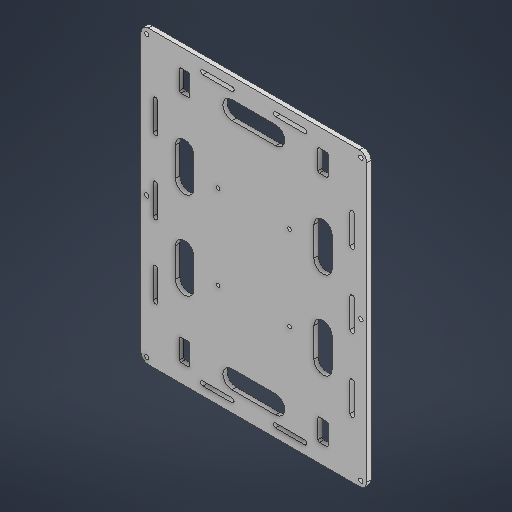
# Autodesk Inventor part: Top
Saved by Autodesk Inventor 2026.3 (Build 303398000, 398)
## iProperties
Created: 2026-07-17
Part Number: Top
Material: Generic
Document SubType Name: Modeling
Designer: nose
Density: 1 g/cm^3
Appearance: Default
Author: nose
Autodesk Inventor part; units mm, degrees
ref_plane "YZ Plane" through (0, 0, 0) normal (1, 0, 0) x (0, 1, 0)
ref_plane "XZ Plane" through (0, 0, 0) normal (0, 1, 0) x (-1, 0, 0)
ref_plane "XY Plane" through (0, 0, 0) normal (0, 0, 1) x (1, 0, 0)
sketch "Sketch1" plane through (0, 0, 0) normal (0, 0, 1) x (1, 0, 0)
  line L0 (72.5, -100) -> (-72.5, -100)
  line L1 (-77.5, -95) -> (-77.5, 95)
  line L2 (-72.5, 100) -> (72.5, 100)
  line L3 (77.5, 95) -> (77.5, -95)
  line L4 (77.5, -100) -> (-77.5, 100) construction
  line L5 (-77.5, -100) -> (77.5, 100) construction
  arc A0 (-72.5, 100) -> (-77.5, 95) centre (-72.5, 95) ccw
  arc A1 (77.5, 95) -> (72.5, 100) centre (72.5, 95) ccw
  arc A2 (72.5, -100) -> (77.5, -95) centre (72.5, -95) ccw
  arc A3 (-77.5, -95) -> (-72.5, -100) centre (-72.5, -95) ccw
  point P0 (0, 0)
  dimension "d0" = 155
  dimension "d1" = 200
  dimension "d2" = 5
  constraints: 12 end point, 8 point on circle, 8 point on line, 8 tangent, 4 centre point, 3 equal radius, 2 midpoint, 2 parallel, 1 horizontal, 1 perpendicular
  measures "d0" distance of L4.end L5.end
  measures "d1" distance of L5.start L4.end
  measures "d2" radius of A0
extrude "base" add sketch "Sketch1" along normal blind 3
sketch "Sketch2" plane through (0, 0, 3) normal (0, 0, 1) x (1, 0, 0)
  line L0 (-90.3018, 80) -> (-26.5899, 80) construction
  line L1 (-63.5, 59.4965) -> (-63.5, 108.4491) construction
  line L2 (-45, 72.5) -> (-50, 72.5)
  line L3 (-51, 73.5) -> (-51, 86.5)
  line L4 (-50, 87.5) -> (-45, 87.5)
  line L5 (-44, 86.5) -> (-44, 73.5)
  line L6 (-44, 72.5) -> (-51, 87.5) construction
  line L7 (-51, 72.5) -> (-44, 87.5) construction
  arc A0 (-50, 87.5) -> (-51, 86.5) centre (-50, 86.5) ccw
  arc A1 (-44, 86.5) -> (-45, 87.5) centre (-45, 86.5) ccw
  arc A2 (-45, 72.5) -> (-44, 73.5) centre (-45, 73.5) ccw
  arc A3 (-51, 73.5) -> (-50, 72.5) centre (-50, 73.5) ccw
  line L8 (0, -165.9432) -> (0, 165.9432) construction
  line L9 (-120.5021, 0) -> (120.5021, 0) construction
  arc A4 (50, 72.5) -> (51, 73.5) centre (50, 73.5) ccw
  line L10 (45, 72.5) -> (50, 72.5)
  line L11 (51, 73.5) -> (51, 86.5)
  arc A5 (51, 86.5) -> (50, 87.5) centre (50, 86.5) ccw
  line L12 (44, 86.5) -> (44, 73.5)
  line L13 (50, 87.5) -> (45, 87.5)
  line L14 (51, 72.5) -> (44, 87.5) construction
  line L15 (44, 72.5) -> (51, 87.5) construction
  arc A6 (45, 87.5) -> (44, 86.5) centre (45, 86.5) ccw
  arc A7 (44, 73.5) -> (45, 72.5) centre (45, 73.5) ccw
  line L16 (45, -72.5) -> (50, -72.5)
  line L17 (-45, -72.5) -> (-50, -72.5)
  line L18 (-44, -86.5) -> (-44, -73.5)
  line L19 (-50, -87.5) -> (-45, -87.5)
  line L20 (-51, -73.5) -> (-51, -86.5)
  line L21 (-44, -72.5) -> (-51, -87.5) construction
  arc A8 (51, -73.5) -> (50, -72.5) centre (50, -73.5) ccw
  arc A9 (45, -72.5) -> (44, -73.5) centre (45, -73.5) ccw
  line L22 (51, -73.5) -> (51, -86.5)
  line L23 (44, -86.5) -> (44, -73.5)
  line L24 (50, -87.5) -> (45, -87.5)
  line L25 (51, -72.5) -> (44, -87.5) construction
  arc A10 (50, -87.5) -> (51, -86.5) centre (50, -86.5) ccw
  arc A11 (44, -86.5) -> (45, -87.5) centre (45, -86.5) ccw
  line L26 (44, -72.5) -> (51, -87.5) construction
  arc A12 (-44, -73.5) -> (-45, -72.5) centre (-45, -73.5) ccw
  arc A13 (-45, -87.5) -> (-44, -86.5) centre (-45, -86.5) ccw
  line L27 (-51, -72.5) -> (-44, -87.5) construction
  arc A14 (-51, -86.5) -> (-50, -87.5) centre (-50, -86.5) ccw
  arc A15 (-50, -72.5) -> (-51, -73.5) centre (-50, -73.5) ccw
  point P0 (0, 0)
  point P1 (-47.5, 80)
  point P2 (-47.5, 72.5)
  point P3 (47.5, 72.5)
  point P4 (47.5, 80)
  point P5 (63.5, 59.4965)
  point P6 (47.5, -72.5)
  point P7 (-26.5899, -80)
  point P8 (-47.5, -80)
  point P9 (47.5, -80)
  point P10 (-47.5, -72.5)
  dimension "d12" = 63.5
  dimension "d13" = 80
  dimension "d11" = 7
  dimension "d9" = 15
  dimension "d8" = 1
  dimension "d7" = 1
  dimension "d6" = 1
  dimension "d5" = 1
  constraints: 56 end point, 56 symmetric about line, 33 point on line, 32 point on circle, 16 centre point, 8 tangent, 5 midpoint, 3 horizontal, 2 parallel, 2 vertical, 1 perpendicular, 12 other
  measures "d12" distance from line of point (0, 0) L1
  measures "d13" distance from line of point (0, 0) L0
  measures "d11" distance of L6.end L7.end
  measures "d9" distance from line of point (-47.5, 72.5) L4
  measures "d8" radius of A0
  measures "d7" radius of A1
  measures "d6" radius of A2
  measures "d5" radius of A3
extrude "motor_mount" cut sketch "Sketch2" against normal through all
sketch "Sketch4" plane through (0, 0, 3) normal (0, 0, 1) x (1, 0, 0)
  line L0 (24.5, -29) -> (-24.5, -29) construction
  line L1 (-24.5, -29) -> (-24.5, 29) construction
  line L2 (-24.5, 29) -> (24.5, 29) construction
  line L3 (24.5, 29) -> (24.5, -29) construction
  line L4 (24.5, -29) -> (-24.5, 29) construction
  line L5 (-24.5, -29) -> (24.5, 29) construction
  circle A0 centre (-24.5, 29) radius 1.25
  circle A1 centre (-24.5, -29) radius 1.25
  circle A2 centre (24.5, -29) radius 1.25
  circle A3 centre (24.5, 29) radius 1.25
  point P0 (0, 0)
  dimension "d32" = 49
  dimension "d33" = 58
  dimension "d34" = 2.5
  dimension "d35" = 2.5
  dimension "d36" = 2.5
  dimension "d37" = 2.5
  constraints: 12 end point, 4 centre point, 4 coincident, 2 midpoint, 2 parallel, 1 horizontal, 1 perpendicular
  measures "d32" distance of L1.end L2.end
  measures "d33" distance of L0.end L1.end
  measures "d34" diameter of A0
  measures "d35" diameter of A1
  measures "d36" diameter of A2
  measures "d37" diameter of A3
extrude "rpi_mount" cut sketch "Sketch4" against normal through all
sketch "Sketch5" plane through (0, 0, 3) normal (0, 0, 1) x (1, 0, 0)
  line L0 (-15, 80) -> (15, 80) construction
  line L1 (-15, 73.75) -> (15, 73.75)
  line L2 (15, 86.25) -> (-15, 86.25)
  arc A0 (-15, 86.25) -> (-15, 73.75) centre (-15, 80) ccw
  arc A1 (15, 73.75) -> (15, 86.25) centre (15, 80) ccw
  line L3 (-47.5, 20) -> (-47.5, 40) construction
  line L4 (-41.25, 20) -> (-41.25, 40)
  line L5 (-53.75, 40) -> (-53.75, 20)
  arc A2 (-53.75, 20) -> (-41.25, 20) centre (-47.5, 20) ccw
  arc A3 (-41.25, 40) -> (-53.75, 40) centre (-47.5, 40) ccw
  line L6 (-47.5, 30) -> (-27.5, 30) construction
  line L7 (-77.5, 95) -> (-77.5, -95) projected
  line L8 (72.5, 100) -> (-72.5, 100) projected
  line L9 (0, 164.0736) -> (0, -168.6299) construction
  line L10 (-194.4712, 0) -> (266.7344, 0) construction
  line L11 (-15, -80) -> (15, -80) construction
  line L12 (-15, -73.75) -> (15, -73.75)
  line L13 (15, -86.25) -> (-15, -86.25)
  arc A4 (-15, -73.75) -> (-15, -86.25) centre (-15, -80) ccw
  arc A5 (15, -86.25) -> (15, -73.75) centre (15, -80) ccw
  line L14 (-47.5, -20) -> (-47.5, -40) construction
  line L15 (-41.25, -20) -> (-41.25, -40)
  line L16 (-53.75, -40) -> (-53.75, -20)
  arc A6 (-41.25, -20) -> (-53.75, -20) centre (-47.5, -20) ccw
  arc A7 (-53.75, -40) -> (-41.25, -40) centre (-47.5, -40) ccw
  line L17 (-47.5, -30) -> (-27.5, -30) construction
  line L18 (0, -164.0736) -> (0, 168.6299) construction
  line L19 (47.5, 20) -> (47.5, 40) construction
  line L20 (41.25, 20) -> (41.25, 40)
  line L21 (53.75, 40) -> (53.75, 20)
  arc A8 (41.25, 20) -> (53.75, 20) centre (47.5, 20) ccw
  arc A9 (53.75, 40) -> (41.25, 40) centre (47.5, 40) ccw
  line L22 (47.5, 30) -> (27.5, 30) construction
  line L23 (194.4712, 0) -> (-266.7344, 0) construction
  line L24 (47.5, -20) -> (47.5, -40) construction
  line L25 (41.25, -20) -> (41.25, -40)
  line L26 (53.75, -40) -> (53.75, -20)
  arc A10 (41.25, -40) -> (53.75, -40) centre (47.5, -40) ccw
  arc A11 (53.75, -20) -> (41.25, -20) centre (47.5, -20) ccw
  line L27 (47.5, -30) -> (27.5, -30) construction
  point P0 (0, 0)
  point P1 (0, 80)
  point P2 (0, -80)
  dimension "d40" = 15
  dimension "d41" = 12.5
  dimension "d42" = 10
  dimension "d44" = 12.5
  dimension "d45" = 30
  dimension "d46" = 20
  dimension "d47" = 30
  constraints: 64 end point, 35 symmetric about line, 24 point on circle, 12 centre point, 8 tangent, 3 horizontal, 2 midpoint, 2 parallel, 2 vertical, 1 perpendicular, 8 other
  measures "d40" distance of point (0, 80) L0.end
  measures "d41" diameter of A1
  measures "d42" distance of L6.start L3.end
  measures "d44" diameter of A3
  measures "d45" distance from line of L7 L6.start
  measures "d46" distance between parallel lines of L8 L0
  measures "d47" vertical distance of point (0, 0) L6.start
extrude "cable_hole" cut sketch "Sketch5" against normal through all
sketch "Sketch6" plane through (0, 0, 3) normal (0, 0, 1) x (1, 0, 0)
  line L0 (-67.5, -10) -> (-67.5, 10) construction
  line L1 (-66, -10) -> (-66, 10)
  line L2 (-69, 10) -> (-69, -10)
  arc A0 (-69, -10) -> (-66, -10) centre (-67.5, -10) ccw
  arc A1 (-66, 10) -> (-69, 10) centre (-67.5, 10) ccw
  line L3 (-67.5, -100) -> (-67.5, 100) construction
  line L4 (72.5, 100) -> (-72.5, 100) projected
  line L5 (-77.5, 95) -> (-77.5, -95) projected
  line L6 (-67.5, 40) -> (-67.5, 60) construction
  line L7 (-66, 40) -> (-66, 60)
  line L8 (-69, 60) -> (-69, 40)
  arc A2 (-69, 40) -> (-66, 40) centre (-67.5, 40) ccw
  arc A3 (-66, 60) -> (-69, 60) centre (-67.5, 60) ccw
  line L9 (-67.5, -59.218) -> (-67.5, 159.218) construction
  line L10 (-67.5, -60) -> (-67.5, -40) construction
  line L11 (-66, -60) -> (-66, -40)
  line L12 (-69, -40) -> (-69, -60)
  arc A4 (-69, -60) -> (-66, -60) centre (-67.5, -60) ccw
  arc A5 (-66, -40) -> (-69, -40) centre (-67.5, -40) ccw
  line L13 (-67.5, -139.2071) -> (-67.5, 39.2071) construction
  line L14 (-128.024, 0) -> (128.024, 0) construction
  line L15 (0, -161.5039) -> (0, 161.5039) construction
  line L16 (67.5, -10) -> (67.5, 10) construction
  line L17 (66, -10) -> (66, 10)
  line L18 (69, 10) -> (69, -10)
  arc A6 (66, -10) -> (69, -10) centre (67.5, -10) ccw
  arc A7 (69, 10) -> (66, 10) centre (67.5, 10) ccw
  line L19 (67.5, -100) -> (67.5, 100) construction
  line L20 (67.5, 40) -> (67.5, 60) construction
  line L21 (66, 40) -> (66, 60)
  line L22 (69, 60) -> (69, 40)
  arc A8 (66, 40) -> (69, 40) centre (67.5, 40) ccw
  arc A9 (69, 60) -> (66, 60) centre (67.5, 60) ccw
  line L23 (67.5, -59.218) -> (67.5, 159.218) construction
  line L24 (67.5, -60) -> (67.5, -40) construction
  line L25 (66, -60) -> (66, -40)
  line L26 (69, -40) -> (69, -60)
  arc A10 (66, -60) -> (69, -60) centre (67.5, -60) ccw
  arc A11 (69, -40) -> (66, -40) centre (67.5, -40) ccw
  line L27 (67.5, -139.2071) -> (67.5, 39.2071) construction
  line L28 (128.024, 0) -> (-128.024, 0) construction
  line L29 (77.5, 92.5) -> (-77.5, 92.5) construction
  line L30 (-35, 92.5) -> (-15, 92.5) construction
  line L31 (-35, 91) -> (-15, 91)
  line L32 (-15, 94) -> (-35, 94)
  arc A12 (-35, 94) -> (-35, 91) centre (-35, 92.5) ccw
  arc A13 (-15, 91) -> (-15, 94) centre (-15, 92.5) ccw
  line L33 (15, 92.5) -> (35, 92.5) construction
  line L34 (15, 91) -> (35, 91)
  line L35 (35, 94) -> (15, 94)
  arc A14 (15, 94) -> (15, 91) centre (15, 92.5) ccw
  arc A15 (35, 91) -> (35, 94) centre (35, 92.5) ccw
  line L36 (-35, -92.5) -> (-15, -92.5) construction
  line L37 (-35, -91) -> (-15, -91)
  line L38 (-15, -94) -> (-35, -94)
  arc A16 (-35, -91) -> (-35, -94) centre (-35, -92.5) ccw
  arc A17 (-15, -94) -> (-15, -91) centre (-15, -92.5) ccw
  line L39 (15, -92.5) -> (35, -92.5) construction
  line L40 (15, -91) -> (35, -91)
  line L41 (35, -94) -> (15, -94)
  arc A18 (15, -91) -> (15, -94) centre (15, -92.5) ccw
  arc A19 (35, -94) -> (35, -91) centre (35, -92.5) ccw
  point P0 (0, 0)
  point P1 (-67.5, 0)
  point P2 (-67.5, 50)
  point P3 (-67.5, -50)
  point P4 (67.5, 0)
  point P5 (67.5, 50)
  point P6 (67.5, -50)
  point P7 (0, 92.5)
  point P8 (-25, 92.5)
  point P9 (25, 92.5)
  point P10 (0, -92.5)
  point P11 (-25, -92.5)
  point P12 (25, -92.5)
  dimension "d50" = 10
  dimension "d51" = 3
  dimension "d52" = 10
  dimension "d53" = 10
  dimension "d54" = 3
  dimension "d55" = 10
  dimension "d56" = 3
  dimension "d58" = 50
  dimension "d59" = 50
  dimension "d60" = 7.5
  dimension "d61" = 10
  dimension "d62" = 3
  dimension "d63" = 10
  dimension "d64" = 3
  dimension "d66" = 25
  dimension "d67" = 25
  constraints: 100 end point, 44 symmetric about line, 40 point on circle, 20 centre point, 20 tangent, 13 point on line, 11 midpoint, 7 vertical, 5 parallel, 1 horizontal, 1 perpendicular, 10 other
  measures "d50" distance of point (-67.5, 0) L0.end
  measures "d51" diameter of A1
  measures "d52" distance between parallel lines of L5 L3
  measures "d53" distance of point (-67.5, 50) L6.end
  measures "d54" diameter of A3
  measures "d55" distance of point (-67.5, -50) L10.end
  measures "d56" diameter of A5
  measures "d58" distance of point (-67.5, 50) point (-67.5, 0)
  measures "d59" distance of point (-67.5, -50) point (-67.5, 0)
  measures "d60" distance between parallel lines of L29 L4
  measures "d61" distance of point (-25, 92.5) L30.end
  measures "d62" diameter of A13
  measures "d63" distance of point (25, 92.5) L33.end
  measures "d64" diameter of A15
  measures "d66" distance of point (25, 92.5) point (0, 92.5)
  measures "d67" distance of point (-25, 92.5) point (0, 92.5)
extrude "screw_mouting" cut sketch "Sketch6" against normal through all
sketch "Sketch7" plane through (0, 0, 3) normal (0, 0, 1) x (1, 0, 0)
  circle A0 centre (-73.5, 96) radius 1.5
  line L0 (0, -163.8328) -> (0, 163.8328) construction
  line L1 (-154.6878, 0) -> (154.6878, 0) construction
  circle A1 centre (73.5, 96) radius 1.5
  circle A2 centre (-73.5, -96) radius 1.5
  circle A3 centre (73.5, -96) radius 1.5
  circle A4 centre (-73.5, 0) radius 1.5
  line L2 (-77.5, 95) -> (-77.5, -95)
  circle A5 centre (73.5, 0) radius 1.5
  point P0 (0, 0)
  dimension "d72" = 3
  dimension "d74" = 73.5
  dimension "d73" = 96
  dimension "d70" = 3
  dimension "d71" = 4
  constraints: 6 centre point, 6 end point, 4 symmetric about line, 2 midpoint, 1 horizontal, 1 point on line, 1 vertical, 4 other
  measures "d72" diameter of A0
  measures "d74" horizontal distance of point (0, 0) A0.centre
  measures "d73" vertical distance of point (0, 0) A0.centre
  measures "d70" diameter of A4
  measures "d71" distance from line of L2 A4.centre
extrude "standoff_mount" cut sketch "Sketch7" against normal through all
equation "\"d0\" = base_width"
equation "\"d1\" = base_length"
equation "\"d2\" = base_fillet"
equation "\"d12\" = 0.5 * d27 - d28"
equation "\"d13\" = 0.5 * d29 - d30"
equation "\"d32\" = rpi_hole_width"
equation "\"d33\" = rpi_hole_length"
equation "\"d34\" = rpi_hole_dia"
equation "\"d35\" = rpi_hole_dia"
equation "\"d36\" = rpi_hole_dia"
equation "\"d37\" = rpi_hole_dia"
equation "\"d50\" = screw_mouting_length"
equation "\"d51\" = screw_mouting_dia"
equation "\"d53\" = screw_mouting_length"
equation "\"d54\" = screw_mouting_dia"
equation "\"d55\" = screw_mouting_length"
equation "\"d56\" = screw_mouting_dia"
equation "\"d58\" = screw_mouting_y_offset"
equation "\"d59\" = screw_mouting_y_offset"
equation "\"d60\" = screw_mouting_edge_offset"
equation "\"d61\" = screw_mouting_length"
equation "\"d62\" = screw_mouting_dia"
equation "\"d63\" = screw_mouting_length"
equation "\"d64\" = screw_mouting_dia"
equation "\"d66\" = screw_mouting_x_offset"
equation "\"d67\" = screw_mouting_x_offset"
equation "\"d74\" = 0.5 * d80 - d78"
equation "\"d73\" = 0.5 * d79 - d78"
equation "\"d71\" = d78"
equation "\"rpi_hole_width\" = 49"
equation "\"rpi_hole_length\" = 58"
equation "\"rpi_hole_dia\" = 2.5"
equation "\"screw_mouting_x_offset\" = 25"
equation "\"screw_mouting_y_offset\" = 50"
equation "\"screw_mouting_dia\" = 3"
equation "\"screw_mouting_length\" = 10"
equation "\"screw_mouting_edge_offset\" = 7.5"
equation "\"base_width\" = 155"
equation "\"base_length\" = 200"
equation "\"base_fillet\" = 5"
equation "\"d78\" = 4"
equation "\"d27\" = 155"
equation "\"d28\" = 14"
equation "\"d29\" = 200"
equation "\"d30\" = 20"
equation "\"d80\" = 155"
equation "\"d79\" = 200"
body "Solid1"
